Autodesk Fusion 360 part; units mm, degrees
(part 9 of 10)
equation "d738 = abs(( frameZ + 20 mm - ( 0 mm ) ) * -1)"
equation "d739 = abs(( frameZ + 20 mm - ( profileLip ) ) * -1)"
equation "d740 = abs(( ( mountInset ) - ( -profileCavity / 2 ) ) * 1)"
equation "d741 = abs(( frameZ + 20 mm - ( profileTaperStart ) ) * -1)"
equation "d742 = abs(( ( mountInset ) - ( -profileFloor / 2 ) ) * 1)"
equation "d743 = abs(( frameZ + 20 mm - ( profileDepth ) ) * -1)"
equation "d744 = abs(( ( mountInset ) - ( profileFloor / 2 ) ) * 1)"
equation "d745 = abs(( ( mountInset ) - ( profileCavity / 2 ) ) * 1)"
equation "d746 = abs(( ( mountInset ) - ( profileMouth / 2 ) ) * 1)"
equation "d747 = ( 2 * panelHeight - 2 * mountInset + 20 mm ) * 1.0"
equation "d749 = ( mountInset - 10 mm ) * 1.0"
equation "d751 = abs(( ( mountInset ) - 10 mm + ( 0 mm ) ) * 1)"
equation "d752 = abs(( frameZ + 10 mm - ( -profileMouth / 2 ) ) * -1)"
equation "d753 = abs(( ( mountInset ) - 10 mm + ( profileLip ) ) * 1)"
equation "d754 = abs(( frameZ + 10 mm - ( -profileCavity / 2 ) ) * -1)"
equation "d755 = abs(( ( mountInset ) - 10 mm + ( profileTaperStart ) ) * 1)"
equation "d756 = abs(( ( mountInset ) - 10 mm + ( profileDepth ) ) * 1)"
equation "d757 = abs(( frameZ + 10 mm - ( -profileFloor / 2 ) ) * -1)"
equation "d758 = abs(( frameZ + 10 mm - ( profileFloor / 2 ) ) * -1)"
equation "d759 = abs(( frameZ + 10 mm - ( profileCavity / 2 ) ) * -1)"
equation "d760 = abs(( frameZ + 10 mm - ( profileMouth / 2 ) ) * -1)"
equation "d761 = ( 2 * panelHeight - 2 * mountInset + 20 mm ) * 1.0"
equation "d763 = ( mountInset - 10 mm ) * 1.0"
equation "d765 = abs(( mountInset ) * 1)"
equation "d766 = abs(( frameZ + 10 mm ) * -1)"
equation "d767 = profileBore"
equation "d768 = ( 2 * panelHeight - 2 * mountInset + 20 mm ) * 1.0"
equation "d770 = ( mountInset - 10 mm ) * 1.0"
equation "d772 = abs(( ( panelWidth ) - 10 mm ) * 1)"
equation "d773 = abs(( frameZ ) * -1)"
equation "d774 = abs(( ( panelWidth ) + 10 mm ) * 1)"
equation "d775 = abs(( frameZ + 20 mm ) * -1)"
equation "d776 = ( 2 * panelHeight - 2 * mountInset + 20 mm ) * 1.0"
equation "d778 = ( mountInset - 10 mm ) * 1.0"
equation "d780 = abs(( ( panelWidth ) + ( -profileMouth / 2 ) ) * 1)"
equation "d781 = abs(( frameZ + ( 0 mm ) ) * -1)"
equation "d782 = abs(( frameZ + ( profileLip ) ) * -1)"
equation "d783 = abs(( ( panelWidth ) + ( -profileCavity / 2 ) ) * 1)"
equation "d784 = abs(( frameZ + ( profileTaperStart ) ) * -1)"
equation "d785 = abs(( ( panelWidth ) + ( -profileFloor / 2 ) ) * 1)"
equation "d786 = abs(( frameZ + ( profileDepth ) ) * -1)"
equation "d787 = abs(( ( panelWidth ) + ( profileFloor / 2 ) ) * 1)"
equation "d788 = abs(( ( panelWidth ) + ( profileCavity / 2 ) ) * 1)"
equation "d789 = abs(( ( panelWidth ) + ( profileMouth / 2 ) ) * 1)"
equation "d790 = ( 2 * panelHeight - 2 * mountInset + 20 mm ) * 1.0"
equation "d792 = ( mountInset - 10 mm ) * 1.0"
equation "d794 = abs(( ( panelWidth ) + 10 mm - ( 0 mm ) ) * 1)"
equation "d795 = abs(( frameZ + 10 mm + ( -profileMouth / 2 ) ) * -1)"
equation "d796 = abs(( ( panelWidth ) + 10 mm - ( profileLip ) ) * 1)"
equation "d797 = abs(( frameZ + 10 mm + ( -profileCavity / 2 ) ) * -1)"
equation "d798 = abs(( ( panelWidth ) + 10 mm - ( profileTaperStart ) ) * 1)"
equation "d799 = abs(( ( panelWidth ) + 10 mm - ( profileDepth ) ) * 1)"
equation "d800 = abs(( frameZ + 10 mm + ( -profileFloor / 2 ) ) * -1)"
equation "d801 = abs(( frameZ + 10 mm + ( profileFloor / 2 ) ) * -1)"
equation "d802 = abs(( frameZ + 10 mm + ( profileCavity / 2 ) ) * -1)"
equation "d803 = abs(( frameZ + 10 mm + ( profileMouth / 2 ) ) * -1)"
equation "d804 = ( 2 * panelHeight - 2 * mountInset + 20 mm ) * 1.0"
equation "d806 = ( mountInset - 10 mm ) * 1.0"
equation "d808 = abs(( ( panelWidth ) - ( -profileMouth / 2 ) ) * 1)"
equation "d809 = abs(( frameZ + 20 mm - ( 0 mm ) ) * -1)"
equation "d810 = abs(( frameZ + 20 mm - ( profileLip ) ) * -1)"
equation "d811 = abs(( ( panelWidth ) - ( -profileCavity / 2 ) ) * 1)"
equation "d812 = abs(( frameZ + 20 mm - ( profileTaperStart ) ) * -1)"
equation "d813 = abs(( ( panelWidth ) - ( -profileFloor / 2 ) ) * 1)"
equation "d814 = abs(( frameZ + 20 mm - ( profileDepth ) ) * -1)"
equation "d815 = abs(( ( panelWidth ) - ( profileFloor / 2 ) ) * 1)"
equation "d816 = abs(( ( panelWidth ) - ( profileCavity / 2 ) ) * 1)"
equation "d817 = abs(( ( panelWidth ) - ( profileMouth / 2 ) ) * 1)"
equation "d818 = ( 2 * panelHeight - 2 * mountInset + 20 mm ) * 1.0"
equation "d820 = ( mountInset - 10 mm ) * 1.0"
equation "d822 = abs(( ( panelWidth ) - 10 mm + ( 0 mm ) ) * 1)"
equation "d823 = abs(( frameZ + 10 mm - ( -profileMouth / 2 ) ) * -1)"
equation "d824 = abs(( ( panelWidth ) - 10 mm + ( profileLip ) ) * 1)"
equation "d825 = abs(( frameZ + 10 mm - ( -profileCavity / 2 ) ) * -1)"
equation "d826 = abs(( ( panelWidth ) - 10 mm + ( profileTaperStart ) ) * 1)"
equation "d827 = abs(( ( panelWidth ) - 10 mm + ( profileDepth ) ) * 1)"
equation "d828 = abs(( frameZ + 10 mm - ( -profileFloor / 2 ) ) * -1)"
equation "d829 = abs(( frameZ + 10 mm - ( profileFloor / 2 ) ) * -1)"
equation "d830 = abs(( frameZ + 10 mm - ( profileCavity / 2 ) ) * -1)"
equation "d831 = abs(( frameZ + 10 mm - ( profileMouth / 2 ) ) * -1)"
equation "d832 = ( 2 * panelHeight - 2 * mountInset + 20 mm ) * 1.0"
equation "d834 = ( mountInset - 10 mm ) * 1.0"
equation "d836 = abs(( panelWidth ) * 1)"
equation "d837 = abs(( frameZ + 10 mm ) * -1)"
equation "d838 = profileBore"
equation "d839 = ( 2 * panelHeight - 2 * mountInset + 20 mm ) * 1.0"
equation "d841 = ( mountInset - 10 mm ) * 1.0"
equation "d843 = abs(( ( 2 * panelWidth - mountInset ) - 10 mm ) * 1)"
equation "d844 = abs(( frameZ ) * -1)"
equation "d845 = abs(( ( 2 * panelWidth - mountInset ) + 10 mm ) * 1)"
equation "d846 = abs(( frameZ + 20 mm ) * -1)"
equation "d847 = ( 2 * panelHeight - 2 * mountInset + 20 mm ) * 1.0"
equation "d849 = ( mountInset - 10 mm ) * 1.0"
equation "d851 = abs(( ( 2 * panelWidth - mountInset ) + ( -profileMouth / 2 ) ) * 1)"
equation "d852 = abs(( frameZ + ( 0 mm ) ) * -1)"
equation "d853 = abs(( frameZ + ( profileLip ) ) * -1)"
equation "d854 = abs(( ( 2 * panelWidth - mountInset ) + ( -profileCavity / 2 ) ) * 1)"
equation "d855 = abs(( frameZ + ( profileTaperStart ) ) * -1)"
equation "d856 = abs(( ( 2 * panelWidth - mountInset ) + ( -profileFloor / 2 ) ) * 1)"
equation "d857 = abs(( frameZ + ( profileDepth ) ) * -1)"
equation "d858 = abs(( ( 2 * panelWidth - mountInset ) + ( profileFloor / 2 ) ) * 1)"
equation "d859 = abs(( ( 2 * panelWidth - mountInset ) + ( profileCavity / 2 ) ) * 1)"
equation "d860 = abs(( ( 2 * panelWidth - mountInset ) + ( profileMouth / 2 ) ) * 1)"
equation "d861 = ( 2 * panelHeight - 2 * mountInset + 20 mm ) * 1.0"
equation "d863 = ( mountInset - 10 mm ) * 1.0"
equation "d865 = abs(( ( 2 * panelWidth - mountInset ) + 10 mm - ( 0 mm ) ) * 1)"
equation "d866 = abs(( frameZ + 10 mm + ( -profileMouth / 2 ) ) * -1)"
equation "d867 = abs(( ( 2 * panelWidth - mountInset ) + 10 mm - ( profileLip ) ) * 1)"
equation "d868 = abs(( frameZ + 10 mm + ( -profileCavity / 2 ) ) * -1)"
equation "d869 = abs(( ( 2 * panelWidth - mountInset ) + 10 mm - ( profileTaperStart ) ) * 1)"
equation "d870 = abs(( ( 2 * panelWidth - mountInset ) + 10 mm - ( profileDepth ) ) * 1)"
equation "d871 = abs(( frameZ + 10 mm + ( -profileFloor / 2 ) ) * -1)"
equation "d872 = abs(( frameZ + 10 mm + ( profileFloor / 2 ) ) * -1)"
equation "d873 = abs(( frameZ + 10 mm + ( profileCavity / 2 ) ) * -1)"
equation "d874 = abs(( frameZ + 10 mm + ( profileMouth / 2 ) ) * -1)"
equation "d875 = ( 2 * panelHeight - 2 * mountInset + 20 mm ) * 1.0"
equation "d877 = ( mountInset - 10 mm ) * 1.0"
equation "d879 = abs(( ( 2 * panelWidth - mountInset ) - ( -profileMouth / 2 ) ) * 1)"
equation "d880 = abs(( frameZ + 20 mm - ( 0 mm ) ) * -1)"
equation "d881 = abs(( frameZ + 20 mm - ( profileLip ) ) * -1)"
equation "d882 = abs(( ( 2 * panelWidth - mountInset ) - ( -profileCavity / 2 ) ) * 1)"
equation "d883 = abs(( frameZ + 20 mm - ( profileTaperStart ) ) * -1)"
equation "d884 = abs(( ( 2 * panelWidth - mountInset ) - ( -profileFloor / 2 ) ) * 1)"
equation "d885 = abs(( frameZ + 20 mm - ( profileDepth ) ) * -1)"
equation "d886 = abs(( ( 2 * panelWidth - mountInset ) - ( profileFloor / 2 ) ) * 1)"
equation "d887 = abs(( ( 2 * panelWidth - mountInset ) - ( profileCavity / 2 ) ) * 1)"
equation "d888 = abs(( ( 2 * panelWidth - mountInset ) - ( profileMouth / 2 ) ) * 1)"
equation "d889 = ( 2 * panelHeight - 2 * mountInset + 20 mm ) * 1.0"
equation "d891 = ( mountInset - 10 mm ) * 1.0"
equation "d893 = abs(( ( 2 * panelWidth - mountInset ) - 10 mm + ( 0 mm ) ) * 1)"
equation "d894 = abs(( frameZ + 10 mm - ( -profileMouth / 2 ) ) * -1)"
equation "d895 = abs(( ( 2 * panelWidth - mountInset ) - 10 mm + ( profileLip ) ) * 1)"
equation "d896 = abs(( frameZ + 10 mm - ( -profileCavity / 2 ) ) * -1)"
equation "d897 = abs(( ( 2 * panelWidth - mountInset ) - 10 mm + ( profileTaperStart ) ) * 1)"
equation "d898 = abs(( ( 2 * panelWidth - mountInset ) - 10 mm + ( profileDepth ) ) * 1)"
equation "d899 = abs(( frameZ + 10 mm - ( -profileFloor / 2 ) ) * -1)"
equation "d900 = abs(( frameZ + 10 mm - ( profileFloor / 2 ) ) * -1)"
equation "d901 = abs(( frameZ + 10 mm - ( profileCavity / 2 ) ) * -1)"
equation "d902 = abs(( frameZ + 10 mm - ( profileMouth / 2 ) ) * -1)"
equation "d903 = ( 2 * panelHeight - 2 * mountInset + 20 mm ) * 1.0"
equation "d905 = ( mountInset - 10 mm ) * 1.0"
equation "d907 = abs(( 2 * panelWidth - mountInset ) * 1)"
equation "d908 = abs(( frameZ + 10 mm ) * -1)"
equation "d909 = profileBore"
equation "d910 = ( 2 * panelHeight - 2 * mountInset + 20 mm ) * 1.0"
equation "d912 = ( mountInset + 10 mm ) * 1.0"
equation "d914 = abs(( frameZ ) * -1)"
equation "d915 = abs(( ( mountInset ) - 10 mm ) * 1)"
equation "d916 = abs(( ( mountInset ) + 10 mm ) * 1)"
equation "d917 = abs(( frameZ + 20 mm ) * -1)"
equation "d918 = ( panelWidth - ( mountInset ) - 20 mm ) * 1.0"
equation "d920 = ( mountInset + 10 mm ) * 1.0"
equation "d922 = abs(( frameZ + ( 0 mm ) ) * -1)"
equation "d923 = abs(( ( mountInset ) + ( -profileMouth / 2 ) ) * 1)"
equation "d924 = abs(( frameZ + ( profileLip ) ) * -1)"
equation "d925 = abs(( ( mountInset ) + ( -profileCavity / 2 ) ) * 1)"
equation "d926 = abs(( frameZ + ( profileTaperStart ) ) * -1)"
equation "d927 = abs(( frameZ + ( profileDepth ) ) * -1)"
equation "d928 = abs(( ( mountInset ) + ( -profileFloor / 2 ) ) * 1)"
equation "d929 = abs(( ( mountInset ) + ( profileFloor / 2 ) ) * 1)"
equation "d930 = abs(( ( mountInset ) + ( profileCavity / 2 ) ) * 1)"
equation "d931 = abs(( ( mountInset ) + ( profileMouth / 2 ) ) * 1)"
equation "d932 = ( panelWidth - ( mountInset ) - 20 mm ) * 1.0"
equation "d934 = ( mountInset + 10 mm ) * 1.0"
equation "d936 = abs(( frameZ + 10 mm + ( -profileMouth / 2 ) ) * -1)"
equation "d937 = abs(( ( mountInset ) + 10 mm - ( 0 mm ) ) * 1)"
equation "d938 = abs(( ( mountInset ) + 10 mm - ( profileLip ) ) * 1)"
equation "d939 = abs(( frameZ + 10 mm + ( -profileCavity / 2 ) ) * -1)"
equation "d940 = abs(( ( mountInset ) + 10 mm - ( profileTaperStart ) ) * 1)"
equation "d941 = abs(( frameZ + 10 mm + ( -profileFloor / 2 ) ) * -1)"
equation "d942 = abs(( ( mountInset ) + 10 mm - ( profileDepth ) ) * 1)"
equation "d943 = abs(( frameZ + 10 mm + ( profileFloor / 2 ) ) * -1)"
equation "d944 = abs(( frameZ + 10 mm + ( profileCavity / 2 ) ) * -1)"
equation "d945 = abs(( frameZ + 10 mm + ( profileMouth / 2 ) ) * -1)"
equation "d946 = ( panelWidth - ( mountInset ) - 20 mm ) * 1.0"
equation "d948 = ( mountInset + 10 mm ) * 1.0"
equation "d950 = abs(( frameZ + 20 mm - ( 0 mm ) ) * -1)"
equation "d951 = abs(( ( mountInset ) - ( -profileMouth / 2 ) ) * 1)"
equation "d952 = abs(( frameZ + 20 mm - ( profileLip ) ) * -1)"
equation "d953 = abs(( ( mountInset ) - ( -profileCavity / 2 ) ) * 1)"
equation "d954 = abs(( frameZ + 20 mm - ( profileTaperStart ) ) * -1)"
equation "d955 = abs(( frameZ + 20 mm - ( profileDepth ) ) * -1)"
equation "d956 = abs(( ( mountInset ) - ( -profileFloor / 2 ) ) * 1)"
equation "d957 = abs(( ( mountInset ) - ( profileFloor / 2 ) ) * 1)"
equation "d958 = abs(( ( mountInset ) - ( profileCavity / 2 ) ) * 1)"
equation "d959 = abs(( ( mountInset ) - ( profileMouth / 2 ) ) * 1)"
equation "d960 = ( panelWidth - ( mountInset ) - 20 mm ) * 1.0"
equation "d962 = ( mountInset + 10 mm ) * 1.0"
equation "d964 = abs(( frameZ + 10 mm - ( -profileMouth / 2 ) ) * -1)"
equation "d965 = abs(( ( mountInset ) - 10 mm + ( 0 mm ) ) * 1)"
equation "d966 = abs(( ( mountInset ) - 10 mm + ( profileLip ) ) * 1)"
equation "d967 = abs(( frameZ + 10 mm - ( -profileCavity / 2 ) ) * -1)"
equation "d968 = abs(( ( mountInset ) - 10 mm + ( profileTaperStart ) ) * 1)"
equation "d969 = abs(( frameZ + 10 mm - ( -profileFloor / 2 ) ) * -1)"
equation "d970 = abs(( ( mountInset ) - 10 mm + ( profileDepth ) ) * 1)"
equation "d971 = abs(( frameZ + 10 mm - ( profileFloor / 2 ) ) * -1)"
equation "d972 = abs(( frameZ + 10 mm - ( profileCavity / 2 ) ) * -1)"
equation "d973 = abs(( frameZ + 10 mm - ( profileMouth / 2 ) ) * -1)"
equation "d974 = ( panelWidth - ( mountInset ) - 20 mm ) * 1.0"
equation "d976 = ( mountInset + 10 mm ) * 1.0"
equation "d978 = abs(( frameZ + 10 mm ) * -1)"
equation "d979 = abs(( mountInset ) * 1)"
equation "d980 = profileBore"
equation "d981 = ( panelWidth - ( mountInset ) - 20 mm ) * 1.0"
equation "d983 = ( panelWidth + 10 mm ) * 1.0"
equation "d985 = abs(( frameZ ) * -1)"
equation "d986 = abs(( ( mountInset ) - 10 mm ) * 1)"
equation "d987 = abs(( ( mountInset ) + 10 mm ) * 1)"
equation "d988 = abs(( frameZ + 20 mm ) * -1)"
equation "d989 = ( 2 * panelWidth - mountInset - ( panelWidth ) - 20 mm ) * 1.0"
equation "d991 = ( panelWidth + 10 mm ) * 1.0"
equation "d993 = abs(( frameZ + ( 0 mm ) ) * -1)"
equation "d994 = abs(( ( mountInset ) + ( -profileMouth / 2 ) ) * 1)"
equation "d995 = abs(( frameZ + ( profileLip ) ) * -1)"
equation "d996 = abs(( ( mountInset ) + ( -profileCavity / 2 ) ) * 1)"
equation "d997 = abs(( frameZ + ( profileTaperStart ) ) * -1)"
equation "d998 = abs(( frameZ + ( profileDepth ) ) * -1)"
equation "d999 = abs(( ( mountInset ) + ( -profileFloor / 2 ) ) * 1)"
equation "d1000 = abs(( ( mountInset ) + ( profileFloor / 2 ) ) * 1)"
equation "d1001 = abs(( ( mountInset ) + ( profileCavity / 2 ) ) * 1)"
equation "d1002 = abs(( ( mountInset ) + ( profileMouth / 2 ) ) * 1)"
equation "d1003 = ( 2 * panelWidth - mountInset - ( panelWidth ) - 20 mm ) * 1.0"
equation "d1005 = ( panelWidth + 10 mm ) * 1.0"
equation "d1007 = abs(( frameZ + 10 mm + ( -profileMouth / 2 ) ) * -1)"
equation "d1008 = abs(( ( mountInset ) + 10 mm - ( 0 mm ) ) * 1)"
equation "d1009 = abs(( ( mountInset ) + 10 mm - ( profileLip ) ) * 1)"
equation "d1010 = abs(( frameZ + 10 mm + ( -profileCavity / 2 ) ) * -1)"
equation "d1011 = abs(( ( mountInset ) + 10 mm - ( profileTaperStart ) ) * 1)"
equation "d1012 = abs(( frameZ + 10 mm + ( -profileFloor / 2 ) ) * -1)"
equation "d1013 = abs(( ( mountInset ) + 10 mm - ( profileDepth ) ) * 1)"
equation "d1014 = abs(( frameZ + 10 mm + ( profileFloor / 2 ) ) * -1)"
equation "d1015 = abs(( frameZ + 10 mm + ( profileCavity / 2 ) ) * -1)"
equation "d1016 = abs(( frameZ + 10 mm + ( profileMouth / 2 ) ) * -1)"
equation "d1017 = ( 2 * panelWidth - mountInset - ( panelWidth ) - 20 mm ) * 1.0"
equation "d1019 = ( panelWidth + 10 mm ) * 1.0"
equation "d1021 = abs(( frameZ + 20 mm - ( 0 mm ) ) * -1)"
equation "d1022 = abs(( ( mountInset ) - ( -profileMouth / 2 ) ) * 1)"
equation "d1023 = abs(( frameZ + 20 mm - ( profileLip ) ) * -1)"
equation "d1024 = abs(( ( mountInset ) - ( -profileCavity / 2 ) ) * 1)"
equation "d1025 = abs(( frameZ + 20 mm - ( profileTaperStart ) ) * -1)"
equation "d1026 = abs(( frameZ + 20 mm - ( profileDepth ) ) * -1)"
equation "d1027 = abs(( ( mountInset ) - ( -profileFloor / 2 ) ) * 1)"
equation "d1028 = abs(( ( mountInset ) - ( profileFloor / 2 ) ) * 1)"
equation "d1029 = abs(( ( mountInset ) - ( profileCavity / 2 ) ) * 1)"
equation "d1030 = abs(( ( mountInset ) - ( profileMouth / 2 ) ) * 1)"
equation "d1031 = ( 2 * panelWidth - mountInset - ( panelWidth ) - 20 mm ) * 1.0"
equation "d1033 = ( panelWidth + 10 mm ) * 1.0"
equation "d1035 = abs(( frameZ + 10 mm - ( -profileMouth / 2 ) ) * -1)"
equation "d1036 = abs(( ( mountInset ) - 10 mm + ( 0 mm ) ) * 1)"
equation "d1037 = abs(( ( mountInset ) - 10 mm + ( profileLip ) ) * 1)"
equation "d1038 = abs(( frameZ + 10 mm - ( -profileCavity / 2 ) ) * -1)"
equation "d1039 = abs(( ( mountInset ) - 10 mm + ( profileTaperStart ) ) * 1)"
equation "d1040 = abs(( frameZ + 10 mm - ( -profileFloor / 2 ) ) * -1)"
equation "d1041 = abs(( ( mountInset ) - 10 mm + ( profileDepth ) ) * 1)"
equation "d1042 = abs(( frameZ + 10 mm - ( profileFloor / 2 ) ) * -1)"
equation "d1043 = abs(( frameZ + 10 mm - ( profileCavity / 2 ) ) * -1)"
equation "d1044 = abs(( frameZ + 10 mm - ( profileMouth / 2 ) ) * -1)"
equation "d1045 = ( 2 * panelWidth - mountInset - ( panelWidth ) - 20 mm ) * 1.0"
equation "d1047 = ( panelWidth + 10 mm ) * 1.0"
equation "d1049 = abs(( frameZ + 10 mm ) * -1)"
equation "d1050 = abs(( mountInset ) * 1)"
equation "d1051 = profileBore"
equation "d1052 = ( 2 * panelWidth - mountInset - ( panelWidth ) - 20 mm ) * 1.0"
equation "d1054 = ( mountInset + 10 mm ) * 1.0"
equation "d1056 = abs(( frameZ ) * -1)"
equation "d1057 = abs(( ( 2 * panelHeight - mountInset ) - 10 mm ) * 1)"
equation "d1058 = abs(( ( 2 * panelHeight - mountInset ) + 10 mm ) * 1)"
equation "d1059 = abs(( frameZ + 20 mm ) * -1)"
equation "d1060 = ( panelWidth - ( mountInset ) - 20 mm ) * 1.0"
equation "d1062 = ( mountInset + 10 mm ) * 1.0"
equation "d1064 = abs(( frameZ + ( 0 mm ) ) * -1)"
equation "d1065 = abs(( ( 2 * panelHeight - mountInset ) + ( -profileMouth / 2 ) ) * 1)"
equation "d1066 = abs(( frameZ + ( profileLip ) ) * -1)"
equation "d1067 = abs(( ( 2 * panelHeight - mountInset ) + ( -profileCavity / 2 ) ) * 1)"
equation "d1068 = abs(( frameZ + ( profileTaperStart ) ) * -1)"
equation "d1069 = abs(( frameZ + ( profileDepth ) ) * -1)"
equation "d1070 = abs(( ( 2 * panelHeight - mountInset ) + ( -profileFloor / 2 ) ) * 1)"
equation "d1071 = abs(( ( 2 * panelHeight - mountInset ) + ( profileFloor / 2 ) ) * 1)"
equation "d1072 = abs(( ( 2 * panelHeight - mountInset ) + ( profileCavity / 2 ) ) * 1)"
equation "d1073 = abs(( ( 2 * panelHeight - mountInset ) + ( profileMouth / 2 ) ) * 1)"
equation "d1074 = ( panelWidth - ( mountInset ) - 20 mm ) * 1.0"
equation "d1076 = ( mountInset + 10 mm ) * 1.0"
equation "d1078 = abs(( frameZ + 10 mm + ( -profileMouth / 2 ) ) * -1)"
equation "d1079 = abs(( ( 2 * panelHeight - mountInset ) + 10 mm - ( 0 mm ) ) * 1)"
equation "d1080 = abs(( ( 2 * panelHeight - mountInset ) + 10 mm - ( profileLip ) ) * 1)"
equation "d1081 = abs(( frameZ + 10 mm + ( -profileCavity / 2 ) ) * -1)"
equation "d1082 = abs(( ( 2 * panelHeight - mountInset ) + 10 mm - ( profileTaperStart ) ) * 1)"
equation "d1083 = abs(( frameZ + 10 mm + ( -profileFloor / 2 ) ) * -1)"
equation "d1084 = abs(( ( 2 * panelHeight - mountInset ) + 10 mm - ( profileDepth ) ) * 1)"
equation "d1085 = abs(( frameZ + 10 mm + ( profileFloor / 2 ) ) * -1)"
equation "d1086 = abs(( frameZ + 10 mm + ( profileCavity / 2 ) ) * -1)"
equation "d1087 = abs(( frameZ + 10 mm + ( profileMouth / 2 ) ) * -1)"
equation "d1088 = ( panelWidth - ( mountInset ) - 20 mm ) * 1.0"
equation "d1090 = ( mountInset + 10 mm ) * 1.0"
equation "d1092 = abs(( frameZ + 20 mm - ( 0 mm ) ) * -1)"
equation "d1093 = abs(( ( 2 * panelHeight - mountInset ) - ( -profileMouth / 2 ) ) * 1)"
equation "d1094 = abs(( frameZ + 20 mm - ( profileLip ) ) * -1)"
equation "d1095 = abs(( ( 2 * panelHeight - mountInset ) - ( -profileCavity / 2 ) ) * 1)"
equation "d1096 = abs(( frameZ + 20 mm - ( profileTaperStart ) ) * -1)"
equation "d1097 = abs(( frameZ + 20 mm - ( profileDepth ) ) * -1)"
equation "d1098 = abs(( ( 2 * panelHeight - mountInset ) - ( -profileFloor / 2 ) ) * 1)"
equation "d1099 = abs(( ( 2 * panelHeight - mountInset ) - ( profileFloor / 2 ) ) * 1)"
equation "d1100 = abs(( ( 2 * panelHeight - mountInset ) - ( profileCavity / 2 ) ) * 1)"
equation "d1101 = abs(( ( 2 * panelHeight - mountInset ) - ( profileMouth / 2 ) ) * 1)"
equation "d1102 = ( panelWidth - ( mountInset ) - 20 mm ) * 1.0"
equation "d1104 = ( mountInset + 10 mm ) * 1.0"
equation "d1106 = abs(( frameZ + 10 mm - ( -profileMouth / 2 ) ) * -1)"
equation "d1107 = abs(( ( 2 * panelHeight - mountInset ) - 10 mm + ( 0 mm ) ) * 1)"
equation "d1108 = abs(( ( 2 * panelHeight - mountInset ) - 10 mm + ( profileLip ) ) * 1)"
equation "d1109 = abs(( frameZ + 10 mm - ( -profileCavity / 2 ) ) * -1)"
equation "d1110 = abs(( ( 2 * panelHeight - mountInset ) - 10 mm + ( profileTaperStart ) ) * 1)"
equation "d1111 = abs(( frameZ + 10 mm - ( -profileFloor / 2 ) ) * -1)"
equation "d1112 = abs(( ( 2 * panelHeight - mountInset ) - 10 mm + ( profileDepth ) ) * 1)"
equation "d1113 = abs(( frameZ + 10 mm - ( profileFloor / 2 ) ) * -1)"
equation "d1114 = abs(( frameZ + 10 mm - ( profileCavity / 2 ) ) * -1)"
equation "d1115 = abs(( frameZ + 10 mm - ( profileMouth / 2 ) ) * -1)"
equation "d1116 = ( panelWidth - ( mountInset ) - 20 mm ) * 1.0"
equation "d1118 = ( mountInset + 10 mm ) * 1.0"
equation "d1120 = abs(( frameZ + 10 mm ) * -1)"
equation "d1121 = abs(( 2 * panelHeight - mountInset ) * 1)"
equation "d1122 = profileBore"
equation "d1123 = ( panelWidth - ( mountInset ) - 20 mm ) * 1.0"
equation "d1125 = ( panelWidth + 10 mm ) * 1.0"
equation "d1127 = abs(( frameZ ) * -1)"
equation "d1128 = abs(( ( 2 * panelHeight - mountInset ) - 10 mm ) * 1)"
equation "d1129 = abs(( ( 2 * panelHeight - mountInset ) + 10 mm ) * 1)"
equation "d1130 = abs(( frameZ + 20 mm ) * -1)"
equation "d1131 = ( 2 * panelWidth - mountInset - ( panelWidth ) - 20 mm ) * 1.0"
equation "d1133 = ( panelWidth + 10 mm ) * 1.0"
equation "d1135 = abs(( frameZ + ( 0 mm ) ) * -1)"
equation "d1136 = abs(( ( 2 * panelHeight - mountInset ) + ( -profileMouth / 2 ) ) * 1)"
equation "d1137 = abs(( frameZ + ( profileLip ) ) * -1)"
equation "d1138 = abs(( ( 2 * panelHeight - mountInset ) + ( -profileCavity / 2 ) ) * 1)"
equation "d1139 = abs(( frameZ + ( profileTaperStart ) ) * -1)"
equation "d1140 = abs(( frameZ + ( profileDepth ) ) * -1)"
equation "d1141 = abs(( ( 2 * panelHeight - mountInset ) + ( -profileFloor / 2 ) ) * 1)"
equation "d1142 = abs(( ( 2 * panelHeight - mountInset ) + ( profileFloor / 2 ) ) * 1)"
equation "d1143 = abs(( ( 2 * panelHeight - mountInset ) + ( profileCavity / 2 ) ) * 1)"
equation "d1144 = abs(( ( 2 * panelHeight - mountInset ) + ( profileMouth / 2 ) ) * 1)"
equation "d1145 = ( 2 * panelWidth - mountInset - ( panelWidth ) - 20 mm ) * 1.0"
equation "d1147 = ( panelWidth + 10 mm ) * 1.0"
equation "d1149 = abs(( frameZ + 10 mm + ( -profileMouth / 2 ) ) * -1)"
equation "d1150 = abs(( ( 2 * panelHeight - mountInset ) + 10 mm - ( 0 mm ) ) * 1)"
equation "d1151 = abs(( ( 2 * panelHeight - mountInset ) + 10 mm - ( profileLip ) ) * 1)"
equation "d1152 = abs(( frameZ + 10 mm + ( -profileCavity / 2 ) ) * -1)"
equation "d1153 = abs(( ( 2 * panelHeight - mountInset ) + 10 mm - ( profileTaperStart ) ) * 1)"
equation "d1154 = abs(( frameZ + 10 mm + ( -profileFloor / 2 ) ) * -1)"
equation "d1155 = abs(( ( 2 * panelHeight - mountInset ) + 10 mm - ( profileDepth ) ) * 1)"
equation "d1156 = abs(( frameZ + 10 mm + ( profileFloor / 2 ) ) * -1)"
equation "d1157 = abs(( frameZ + 10 mm + ( profileCavity / 2 ) ) * -1)"
equation "d1158 = abs(( frameZ + 10 mm + ( profileMouth / 2 ) ) * -1)"
equation "d1159 = ( 2 * panelWidth - mountInset - ( panelWidth ) - 20 mm ) * 1.0"
equation "d1161 = ( panelWidth + 10 mm ) * 1.0"
equation "d1163 = abs(( frameZ + 20 mm - ( 0 mm ) ) * -1)"
equation "d1164 = abs(( ( 2 * panelHeight - mountInset ) - ( -profileMouth / 2 ) ) * 1)"
equation "d1165 = abs(( frameZ + 20 mm - ( profileLip ) ) * -1)"
equation "d1166 = abs(( ( 2 * panelHeight - mountInset ) - ( -profileCavity / 2 ) ) * 1)"
equation "d1167 = abs(( frameZ + 20 mm - ( profileTaperStart ) ) * -1)"
equation "d1168 = abs(( frameZ + 20 mm - ( profileDepth ) ) * -1)"
equation "d1169 = abs(( ( 2 * panelHeight - mountInset ) - ( -profileFloor / 2 ) ) * 1)"
equation "d1170 = abs(( ( 2 * panelHeight - mountInset ) - ( profileFloor / 2 ) ) * 1)"
equation "d1171 = abs(( ( 2 * panelHeight - mountInset ) - ( profileCavity / 2 ) ) * 1)"
equation "d1172 = abs(( ( 2 * panelHeight - mountInset ) - ( profileMouth / 2 ) ) * 1)"
equation "d1173 = ( 2 * panelWidth - mountInset - ( panelWidth ) - 20 mm ) * 1.0"
equation "d1175 = ( panelWidth + 10 mm ) * 1.0"
equation "d1177 = abs(( frameZ + 10 mm - ( -profileMouth / 2 ) ) * -1)"
equation "d1178 = abs(( ( 2 * panelHeight - mountInset ) - 10 mm + ( 0 mm ) ) * 1)"
equation "d1179 = abs(( ( 2 * panelHeight - mountInset ) - 10 mm + ( profileLip ) ) * 1)"
equation "d1180 = abs(( frameZ + 10 mm - ( -profileCavity / 2 ) ) * -1)"
equation "d1181 = abs(( ( 2 * panelHeight - mountInset ) - 10 mm + ( profileTaperStart ) ) * 1)"
equation "d1182 = abs(( frameZ + 10 mm - ( -profileFloor / 2 ) ) * -1)"
equation "d1183 = abs(( ( 2 * panelHeight - mountInset ) - 10 mm + ( profileDepth ) ) * 1)"
equation "d1184 = abs(( frameZ + 10 mm - ( profileFloor / 2 ) ) * -1)"
equation "d1185 = abs(( frameZ + 10 mm - ( profileCavity / 2 ) ) * -1)"
equation "d1186 = abs(( frameZ + 10 mm - ( profileMouth / 2 ) ) * -1)"
equation "d1187 = ( 2 * panelWidth - mountInset - ( panelWidth ) - 20 mm ) * 1.0"
equation "d1189 = ( panelWidth + 10 mm ) * 1.0"
equation "d1191 = abs(( frameZ + 10 mm ) * -1)"
equation "d1192 = abs(( 2 * panelHeight - mountInset ) * 1)"
equation "d1193 = profileBore"
equation "d1194 = ( 2 * panelWidth - mountInset - ( panelWidth ) - 20 mm ) * 1.0"
equation "d1300 = -capThickness"
equation "d1302 = abs(mountInset)"
equation "d1303 = abs(mountInset)"
equation "d1304 = capDiameter"
equation "d1305 = capThickness"
equation "d1307 = -capThickness"
equation "d1309 = abs(mountInset)"
equation "d1310 = abs(mountInset)"
equation "d1311 = screwClearance"
equation "d1312 = capThickness"
equation "d1314 = boardThickness"
equation "d1316 = abs(mountInset)"
equation "d1317 = abs(mountInset)"
equation "d1318 = capDiameter"
equation "d1319 = seatThickness"
equation "d1321 = boardThickness"
equation "d1323 = abs(mountInset)"
equation "d1324 = abs(mountInset)"
equation "d1325 = mountBore"
equation "d1326 = seatThickness"
equation "d1328 = boardThickness"
equation "d1330 = abs(mountInset + ( -1 ) * registerOffset)"
equation "d1331 = abs(mountInset + ( -1 ) * registerOffset)"
equation "d1332 = registerPin"
equation "d1333 = -registerPinHeight"
equation "d1335 = boardThickness"
equation "d1337 = abs(mountInset + ( -1 ) * registerOffset)"
equation "d1338 = abs(mountInset + ( 1 ) * registerOffset)"
equation "d1339 = registerPin"
equation "d1340 = -registerPinHeight"
equation "d1342 = boardThickness"
equation "d1344 = abs(mountInset + ( 1 ) * registerOffset)"
equation "d1345 = abs(mountInset + ( -1 ) * registerOffset)"
equation "d1346 = registerPin"
equation "d1347 = -registerPinHeight"
equation "d1349 = boardThickness"
equation "d1351 = abs(mountInset + ( 1 ) * registerOffset)"
equation "d1352 = abs(mountInset + ( 1 ) * registerOffset)"
equation "d1353 = registerPin"
equation "d1354 = -registerPinHeight"
equation "d1356 = abs(mountInset)"
equation "d1357 = abs(mountInset)"
equation "d1359 = boardThickness + seatThickness"
equation "d1361 = boardThickness + seatThickness"
equation "d1363 = abs(mountInset)"
equation "d1364 = abs(mountInset)"
equation "d1366 = hookClearance - seatThickness"
equation "d1368 = abs(mountInset)"
equation "d1369 = abs(mountInset)"
equation "d1370 = screwClearance"
equation "d1371 = frameZ"
equation "d1373 = -capThickness - 3 mm"
equation "d1375 = abs(mountInset)"
equation "d1376 = abs(mountInset)"
equation "d1380 = -capThickness"
equation "d1382 = abs(mountInset)"
equation "d1383 = abs(mountInset)"
equation "d1385 = frameZ + capThickness + 5 mm"
equation "d1387 = frameZ + profileLip"
equation "d1389 = abs(mountInset - nutWidth / 2)"
equation "d1390 = abs(mountInset - nutLength / 2)"
equation "d1391 = nutWidth"
equation "d1392 = nutLength"
equation "d1393 = nutThickness"
equation "d1395 = frameZ + profileLip"
equation "d1397 = abs(mountInset)"
equation "d1398 = abs(mountInset)"
equation "d1400 = nutThickness"
equation "d1402 = -capThickness"
equation "d1404 = abs(mountInset)"
equation "d1405 = abs(panelHeight)"
equation "d1406 = capDiameter"
equation "d1407 = capThickness"
equation "d1409 = -capThickness"
equation "d1411 = abs(mountInset)"
equation "d1412 = abs(panelHeight)"
equation "d1413 = screwClearance"
equation "d1414 = capThickness"
equation "d1416 = boardThickness"
equation "d1418 = abs(mountInset)"
equation "d1419 = abs(panelHeight)"
equation "d1420 = capDiameter"
equation "d1421 = seatThickness"
equation "d1423 = boardThickness"
equation "d1425 = abs(mountInset)"
equation "d1426 = abs(panelHeight)"
equation "d1427 = mountBore"
equation "d1428 = seatThickness"
equation "d1430 = boardThickness"
equation "d1432 = abs(mountInset + ( -1 ) * registerOffset)"
equation "d1433 = abs(panelHeight + ( -1 ) * registerOffset)"
equation "d1434 = registerPin"
equation "d1435 = -registerPinHeight"
equation "d1437 = boardThickness"
equation "d1439 = abs(mountInset + ( -1 ) * registerOffset)"
equation "d1440 = abs(panelHeight + ( 1 ) * registerOffset)"
equation "d1441 = registerPin"
equation "d1442 = -registerPinHeight"
equation "d1444 = boardThickness"
equation "d1446 = abs(mountInset + ( 1 ) * registerOffset)"
equation "d1447 = abs(panelHeight + ( -1 ) * registerOffset)"
equation "d1448 = registerPin"
equation "d1449 = -registerPinHeight"
equation "d1451 = boardThickness"
equation "d1453 = abs(mountInset + ( 1 ) * registerOffset)"
equation "d1454 = abs(panelHeight + ( 1 ) * registerOffset)"
equation "d1455 = registerPin"
equation "d1456 = -registerPinHeight"
equation "d1458 = abs(mountInset)"
equation "d1459 = abs(panelHeight)"
equation "d1461 = boardThickness + seatThickness"
equation "d1463 = boardThickness + seatThickness"
equation "d1465 = abs(mountInset)"
equation "d1466 = abs(panelHeight)"
equation "d1468 = hookClearance - seatThickness"
equation "d1470 = abs(mountInset)"
equation "d1471 = abs(panelHeight)"
equation "d1472 = screwClearance"
equation "d1473 = frameZ"
equation "d1475 = -capThickness - 3 mm"
equation "d1477 = abs(mountInset)"
equation "d1478 = abs(panelHeight)"
equation "d1482 = -capThickness"
equation "d1484 = abs(mountInset)"
equation "d1485 = abs(panelHeight)"
equation "d1487 = frameZ + capThickness + 5 mm"
equation "d1489 = frameZ + profileLip"
equation "d1491 = abs(mountInset - nutWidth / 2)"
equation "d1492 = abs(panelHeight - nutLength / 2)"
equation "d1493 = nutWidth"
equation "d1494 = nutLength"
equation "d1495 = nutThickness"
equation "d1497 = frameZ + profileLip"
equation "d1499 = abs(mountInset)"
equation "d1500 = abs(panelHeight)"
equation "d1502 = nutThickness"
equation "d1504 = -capThickness"
equation "d1506 = abs(mountInset)"
equation "d1507 = abs(2 * panelHeight - mountInset)"
equation "d1508 = capDiameter"
equation "d1509 = capThickness"
equation "d1511 = -capThickness"
equation "d1513 = abs(mountInset)"
equation "d1514 = abs(2 * panelHeight - mountInset)"
equation "d1515 = screwClearance"
equation "d1516 = capThickness"
equation "d1518 = boardThickness"
equation "d1520 = abs(mountInset)"
equation "d1521 = abs(2 * panelHeight - mountInset)"
equation "d1522 = capDiameter"
equation "d1523 = seatThickness"
equation "d1525 = boardThickness"
equation "d1527 = abs(mountInset)"
equation "d1528 = abs(2 * panelHeight - mountInset)"
equation "d1529 = mountBore"
equation "d1530 = seatThickness"
equation "d1532 = boardThickness"
equation "d1534 = abs(mountInset + ( -1 ) * registerOffset)"
equation "d1535 = abs(2 * panelHeight - mountInset + ( -1 ) * registerOffset)"
equation "d1536 = registerPin"
equation "d1537 = -registerPinHeight"
equation "d1539 = boardThickness"
equation "d1541 = abs(mountInset + ( -1 ) * registerOffset)"
equation "d1542 = abs(2 * panelHeight - mountInset + ( 1 ) * registerOffset)"
equation "d1543 = registerPin"
equation "d1544 = -registerPinHeight"
equation "d1546 = boardThickness"
equation "d1548 = abs(mountInset + ( 1 ) * registerOffset)"
equation "d1549 = abs(2 * panelHeight - mountInset + ( -1 ) * registerOffset)"
equation "d1550 = registerPin"
equation "d1551 = -registerPinHeight"
equation "d1553 = boardThickness"
equation "d1555 = abs(mountInset + ( 1 ) * registerOffset)"
equation "d1556 = abs(2 * panelHeight - mountInset + ( 1 ) * registerOffset)"
equation "d1557 = registerPin"
equation "d1558 = -registerPinHeight"
equation "d1560 = abs(mountInset)"
equation "d1561 = abs(2 * panelHeight - mountInset)"
equation "d1563 = boardThickness + seatThickness"
equation "d1565 = boardThickness + seatThickness"
equation "d1567 = abs(mountInset)"
equation "d1568 = abs(2 * panelHeight - mountInset)"
equation "d1570 = hookClearance - seatThickness"
equation "d1572 = abs(mountInset)"
equation "d1573 = abs(2 * panelHeight - mountInset)"
equation "d1574 = screwClearance"
equation "d1575 = frameZ"
equation "d1577 = -capThickness - 3 mm"
equation "d1579 = abs(mountInset)"
equation "d1580 = abs(2 * panelHeight - mountInset)"
equation "d1584 = -capThickness"
equation "d1586 = abs(mountInset)"
equation "d1587 = abs(2 * panelHeight - mountInset)"
equation "d1589 = frameZ + capThickness + 5 mm"
equation "d1591 = frameZ + profileLip"
equation "d1593 = abs(mountInset - nutWidth / 2)"
equation "d1594 = abs(2 * panelHeight - mountInset - nutLength / 2)"
equation "d1595 = nutWidth"
equation "d1596 = nutLength"
equation "d1597 = nutThickness"
equation "d1599 = frameZ + profileLip"
equation "d1601 = abs(mountInset)"
equation "d1602 = abs(2 * panelHeight - mountInset)"
equation "d1604 = nutThickness"
equation "d1606 = -capThickness"
equation "d1608 = abs(panelWidth)"
equation "d1609 = abs(mountInset)"
equation "d1610 = capDiameter"
equation "d1611 = capThickness"
equation "d1613 = -capThickness"
equation "d1615 = abs(panelWidth)"
equation "d1616 = abs(mountInset)"
equation "d1617 = screwClearance"
equation "d1618 = capThickness"
equation "d1620 = boardThickness"
equation "d1622 = abs(panelWidth)"
equation "d1623 = abs(mountInset)"
equation "d1624 = capDiameter"
equation "d1625 = seatThickness"
equation "d1627 = boardThickness"
equation "d1629 = abs(panelWidth)"
equation "d1630 = abs(mountInset)"
equation "d1631 = mountBore"
equation "d1632 = seatThickness"
equation "d1634 = boardThickness"
equation "d1636 = abs(panelWidth + ( -1 ) * registerOffset)"
equation "d1637 = abs(mountInset + ( -1 ) * registerOffset)"
equation "d1638 = registerPin"
equation "d1639 = -registerPinHeight"
equation "d1641 = boardThickness"
equation "d1643 = abs(panelWidth + ( -1 ) * registerOffset)"
equation "d1644 = abs(mountInset + ( 1 ) * registerOffset)"
equation "d1645 = registerPin"
equation "d1646 = -registerPinHeight"
equation "d1648 = boardThickness"
equation "d1650 = abs(panelWidth + ( 1 ) * registerOffset)"
equation "d1651 = abs(mountInset + ( -1 ) * registerOffset)"
equation "d1652 = registerPin"
equation "d1653 = -registerPinHeight"
equation "d1655 = boardThickness"
equation "d1657 = abs(panelWidth + ( 1 ) * registerOffset)"
equation "d1658 = abs(mountInset + ( 1 ) * registerOffset)"
equation "d1659 = registerPin"
equation "d1660 = -registerPinHeight"
equation "d1662 = abs(panelWidth)"
equation "d1663 = abs(mountInset)"
equation "d1665 = boardThickness + seatThickness"
equation "d1667 = boardThickness + seatThickness"
equation "d1669 = abs(panelWidth)"
equation "d1670 = abs(mountInset)"
equation "d1672 = hookClearance - seatThickness"
equation "d1674 = abs(panelWidth)"
equation "d1675 = abs(mountInset)"
equation "d1676 = screwClearance"
equation "d1677 = frameZ"
equation "d1679 = -capThickness - 3 mm"
equation "d1681 = abs(panelWidth)"
equation "d1682 = abs(mountInset)"
equation "d1686 = -capThickness"
equation "d1688 = abs(panelWidth)"
equation "d1689 = abs(mountInset)"
equation "d1691 = frameZ + capThickness + 5 mm"
equation "d1693 = frameZ + profileLip"
equation "d1695 = abs(panelWidth - nutWidth / 2)"
equation "d1696 = abs(mountInset - nutLength / 2)"
equation "d1697 = nutWidth"
equation "d1698 = nutLength"
equation "d1699 = nutThickness"
equation "d1701 = frameZ + profileLip"
equation "d1703 = abs(panelWidth)"
equation "d1704 = abs(mountInset)"
equation "d1706 = nutThickness"
equation "d1708 = -capThickness"
equation "d1710 = abs(panelWidth)"
equation "d1711 = abs(panelHeight)"
equation "d1712 = capDiameter"
equation "d1713 = capThickness"
equation "d1715 = -capThickness"
equation "d1717 = abs(panelWidth)"
equation "d1718 = abs(panelHeight)"
equation "d1719 = screwClearance"
equation "d1720 = capThickness"
equation "d1722 = boardThickness"
equation "d1724 = abs(panelWidth)"
equation "d1725 = abs(panelHeight)"
equation "d1726 = capDiameter"
equation "d1727 = seatThickness"
equation "d1729 = boardThickness"
equation "d1731 = abs(panelWidth)"
equation "d1732 = abs(panelHeight)"
equation "d1733 = mountBore"
equation "d1734 = seatThickness"
equation "d1736 = boardThickness"
equation "d1738 = abs(panelWidth + ( -1 ) * registerOffset)"
equation "d1739 = abs(panelHeight + ( -1 ) * registerOffset)"
equation "d1740 = registerPin"
equation "d1741 = -registerPinHeight"
equation "d1743 = boardThickness"
equation "d1745 = abs(panelWidth + ( -1 ) * registerOffset)"
equation "d1746 = abs(panelHeight + ( 1 ) * registerOffset)"
equation "d1747 = registerPin"
equation "d1748 = -registerPinHeight"
equation "d1750 = boardThickness"
equation "d1752 = abs(panelWidth + ( 1 ) * registerOffset)"
equation "d1753 = abs(panelHeight + ( -1 ) * registerOffset)"
equation "d1754 = registerPin"
equation "d1755 = -registerPinHeight"
equation "d1757 = boardThickness"
equation "d1759 = abs(panelWidth + ( 1 ) * registerOffset)"
equation "d1760 = abs(panelHeight + ( 1 ) * registerOffset)"
equation "d1761 = registerPin"
equation "d1762 = -registerPinHeight"
equation "d1764 = abs(panelWidth)"
equation "d1765 = abs(panelHeight)"
equation "d1767 = boardThickness + seatThickness"
equation "d1769 = boardThickness + seatThickness"
equation "d1771 = abs(panelWidth)"
equation "d1772 = abs(panelHeight)"
equation "d1774 = hookClearance - seatThickness"
equation "d1776 = abs(panelWidth)"
equation "d1777 = abs(panelHeight)"
equation "d1778 = screwClearance"
equation "d1779 = frameZ"
equation "d1781 = -capThickness - 3 mm"
equation "d1783 = abs(panelWidth)"
equation "d1784 = abs(panelHeight)"
equation "d1788 = -capThickness"
equation "d1790 = abs(panelWidth)"
equation "d1791 = abs(panelHeight)"
equation "d1793 = frameZ + capThickness + 5 mm"
equation "d1795 = frameZ + profileLip"
equation "d1797 = abs(panelWidth - nutWidth / 2)"
equation "d1798 = abs(panelHeight - nutLength / 2)"
equation "d1799 = nutWidth"
equation "d1800 = nutLength"
equation "d1801 = nutThickness"
equation "d1803 = frameZ + profileLip"
equation "d1805 = abs(panelWidth)"
equation "d1806 = abs(panelHeight)"
equation "d1808 = nutThickness"
equation "d1810 = -capThickness"
equation "d1812 = abs(panelWidth)"
equation "d1813 = abs(2 * panelHeight - mountInset)"
equation "d1814 = capDiameter"
equation "d1815 = capThickness"
equation "d1817 = -capThickness"
equation "d1819 = abs(panelWidth)"
equation "d1820 = abs(2 * panelHeight - mountInset)"
equation "d1821 = screwClearance"
equation "d1822 = capThickness"
equation "d1824 = boardThickness"
equation "d1826 = abs(panelWidth)"
equation "d1827 = abs(2 * panelHeight - mountInset)"
equation "d1828 = capDiameter"
equation "d1829 = seatThickness"
equation "d1831 = boardThickness"
equation "d1833 = abs(panelWidth)"
equation "d1834 = abs(2 * panelHeight - mountInset)"
equation "d1835 = mountBore"
equation "d1836 = seatThickness"
equation "d1838 = boardThickness"
equation "d1840 = abs(panelWidth + ( -1 ) * registerOffset)"
equation "d1841 = abs(2 * panelHeight - mountInset + ( -1 ) * registerOffset)"
equation "d1842 = registerPin"
equation "d1843 = -registerPinHeight"
equation "d1845 = boardThickness"
equation "d1847 = abs(panelWidth + ( -1 ) * registerOffset)"
equation "d1848 = abs(2 * panelHeight - mountInset + ( 1 ) * registerOffset)"
equation "d1849 = registerPin"
equation "d1850 = -registerPinHeight"
equation "d1852 = boardThickness"
equation "d1854 = abs(panelWidth + ( 1 ) * registerOffset)"
equation "d1855 = abs(2 * panelHeight - mountInset + ( -1 ) * registerOffset)"
equation "d1856 = registerPin"
equation "d1857 = -registerPinHeight"
equation "d1859 = boardThickness"
equation "d1861 = abs(panelWidth + ( 1 ) * registerOffset)"
equation "d1862 = abs(2 * panelHeight - mountInset + ( 1 ) * registerOffset)"
equation "d1863 = registerPin"
equation "d1864 = -registerPinHeight"
equation "d1866 = abs(panelWidth)"
equation "d1867 = abs(2 * panelHeight - mountInset)"
equation "d1869 = boardThickness + seatThickness"
equation "d1871 = boardThickness + seatThickness"
equation "d1873 = abs(panelWidth)"
equation "d1874 = abs(2 * panelHeight - mountInset)"
equation "d1876 = hookClearance - seatThickness"
equation "d1878 = abs(panelWidth)"
equation "d1879 = abs(2 * panelHeight - mountInset)"
equation "d1880 = screwClearance"
equation "d1881 = frameZ"
equation "d1883 = -capThickness - 3 mm"
equation "d1885 = abs(panelWidth)"
equation "d1886 = abs(2 * panelHeight - mountInset)"
equation "d1890 = -capThickness"
equation "d1892 = abs(panelWidth)"
equation "d1893 = abs(2 * panelHeight - mountInset)"
equation "d1895 = frameZ + capThickness + 5 mm"
equation "d1897 = frameZ + profileLip"
equation "d1899 = abs(panelWidth - nutWidth / 2)"
equation "d1900 = abs(2 * panelHeight - mountInset - nutLength / 2)"
equation "d1901 = nutWidth"
equation "d1902 = nutLength"
equation "d1903 = nutThickness"
equation "d1905 = frameZ + profileLip"
equation "d1907 = abs(panelWidth)"
equation "d1908 = abs(2 * panelHeight - mountInset)"
equation "d1910 = nutThickness"
equation "d1912 = -capThickness"
equation "d1914 = abs(2 * panelWidth - mountInset)"
equation "d1915 = abs(mountInset)"
equation "d1916 = capDiameter"
equation "d1917 = capThickness"
equation "d1919 = -capThickness"
equation "d1921 = abs(2 * panelWidth - mountInset)"
equation "d1922 = abs(mountInset)"
equation "d1923 = screwClearance"
equation "d1924 = capThickness"
equation "d1926 = boardThickness"
equation "d1928 = abs(2 * panelWidth - mountInset)"
equation "d1929 = abs(mountInset)"
equation "d1930 = capDiameter"
equation "d1931 = seatThickness"
equation "d1933 = boardThickness"
equation "d1935 = abs(2 * panelWidth - mountInset)"
equation "d1936 = abs(mountInset)"
equation "d1937 = mountBore"
equation "d1938 = seatThickness"
equation "d1940 = boardThickness"
equation "d1942 = abs(2 * panelWidth - mountInset + ( -1 ) * registerOffset)"
equation "d1943 = abs(mountInset + ( -1 ) * registerOffset)"
equation "d1944 = registerPin"
equation "d1945 = -registerPinHeight"
equation "d1947 = boardThickness"
equation "d1949 = abs(2 * panelWidth - mountInset + ( -1 ) * registerOffset)"
equation "d1950 = abs(mountInset + ( 1 ) * registerOffset)"
equation "d1951 = registerPin"
equation "d1952 = -registerPinHeight"
equation "d1954 = boardThickness"
equation "d1956 = abs(2 * panelWidth - mountInset + ( 1 ) * registerOffset)"
equation "d1957 = abs(mountInset + ( -1 ) * registerOffset)"
equation "d1958 = registerPin"
equation "d1959 = -registerPinHeight"
equation "d1961 = boardThickness"
equation "d1963 = abs(2 * panelWidth - mountInset + ( 1 ) * registerOffset)"
equation "d1964 = abs(mountInset + ( 1 ) * registerOffset)"
equation "d1965 = registerPin"
equation "d1966 = -registerPinHeight"
equation "d1968 = abs(2 * panelWidth - mountInset)"
equation "d1969 = abs(mountInset)"
equation "d1971 = boardThickness + seatThickness"
equation "d1973 = boardThickness + seatThickness"
equation "d1975 = abs(2 * panelWidth - mountInset)"
equation "d1976 = abs(mountInset)"
equation "d1978 = hookClearance - seatThickness"
equation "d1980 = abs(2 * panelWidth - mountInset)"
equation "d1981 = abs(mountInset)"
equation "d1982 = screwClearance"
equation "d1983 = frameZ"
equation "d1985 = -capThickness - 3 mm"
equation "d1987 = abs(2 * panelWidth - mountInset)"
equation "d1988 = abs(mountInset)"
equation "d1992 = -capThickness"
equation "d1994 = abs(2 * panelWidth - mountInset)"
equation "d1995 = abs(mountInset)"
equation "d1997 = frameZ + capThickness + 5 mm"
equation "d1999 = frameZ + profileLip"
equation "d2001 = abs(2 * panelWidth - mountInset - nutWidth / 2)"
equation "d2002 = abs(mountInset - nutLength / 2)"
equation "d2003 = nutWidth"
equation "d2004 = nutLength"
equation "d2005 = nutThickness"
equation "d2007 = frameZ + profileLip"
equation "d2009 = abs(2 * panelWidth - mountInset)"
equation "d2010 = abs(mountInset)"
equation "d2012 = nutThickness"
equation "d2014 = -capThickness"
equation "d2016 = abs(2 * panelWidth - mountInset)"
equation "d2017 = abs(panelHeight)"
equation "d2018 = capDiameter"
equation "d2019 = capThickness"
equation "d2021 = -capThickness"
equation "d2023 = abs(2 * panelWidth - mountInset)"
equation "d2024 = abs(panelHeight)"
equation "d2025 = screwClearance"
equation "d2026 = capThickness"
equation "d2028 = boardThickness"
equation "d2030 = abs(2 * panelWidth - mountInset)"
equation "d2031 = abs(panelHeight)"
equation "d2032 = capDiameter"
equation "d2033 = seatThickness"
equation "d2035 = boardThickness"
equation "d2037 = abs(2 * panelWidth - mountInset)"
equation "d2038 = abs(panelHeight)"
equation "d2039 = mountBore"
equation "d2040 = seatThickness"
equation "d2042 = boardThickness"
equation "d2044 = abs(2 * panelWidth - mountInset + ( -1 ) * registerOffset)"
equation "d2045 = abs(panelHeight + ( -1 ) * registerOffset)"
equation "d2046 = registerPin"
equation "d2047 = -registerPinHeight"
equation "d2049 = boardThickness"
equation "d2051 = abs(2 * panelWidth - mountInset + ( -1 ) * registerOffset)"
equation "d2052 = abs(panelHeight + ( 1 ) * registerOffset)"
equation "d2053 = registerPin"
equation "d2054 = -registerPinHeight"
equation "d2056 = boardThickness"
equation "d2058 = abs(2 * panelWidth - mountInset + ( 1 ) * registerOffset)"
equation "d2059 = abs(panelHeight + ( -1 ) * registerOffset)"
equation "d2060 = registerPin"
equation "d2061 = -registerPinHeight"
equation "d2063 = boardThickness"
equation "d2065 = abs(2 * panelWidth - mountInset + ( 1 ) * registerOffset)"
equation "d2066 = abs(panelHeight + ( 1 ) * registerOffset)"
equation "d2067 = registerPin"
equation "d2068 = -registerPinHeight"
equation "d2070 = abs(2 * panelWidth - mountInset)"
equation "d2071 = abs(panelHeight)"
equation "d2073 = boardThickness + seatThickness"
equation "d2075 = boardThickness + seatThickness"
equation "d2077 = abs(2 * panelWidth - mountInset)"
equation "d2078 = abs(panelHeight)"
equation "d2080 = hookClearance - seatThickness"
equation "d2082 = abs(2 * panelWidth - mountInset)"
equation "d2083 = abs(panelHeight)"
equation "d2084 = screwClearance"
equation "d2085 = frameZ"
equation "d2087 = -capThickness - 3 mm"
equation "d2089 = abs(2 * panelWidth - mountInset)"
equation "d2090 = abs(panelHeight)"
equation "d2094 = -capThickness"
equation "d2096 = abs(2 * panelWidth - mountInset)"
equation "d2097 = abs(panelHeight)"
equation "d2099 = frameZ + capThickness + 5 mm"
equation "d2101 = frameZ + profileLip"
equation "d2103 = abs(2 * panelWidth - mountInset - nutWidth / 2)"
equation "d2104 = abs(panelHeight - nutLength / 2)"
equation "d2105 = nutWidth"
equation "d2106 = nutLength"
equation "d2107 = nutThickness"
equation "d2109 = frameZ + profileLip"
equation "d2111 = abs(2 * panelWidth - mountInset)"
equation "d2112 = abs(panelHeight)"
equation "d2114 = nutThickness"
equation "d2116 = -capThickness"
equation "d2118 = abs(2 * panelWidth - mountInset)"
equation "d2119 = abs(2 * panelHeight - mountInset)"
equation "d2120 = capDiameter"
equation "d2121 = capThickness"
equation "d2123 = -capThickness"
equation "d2125 = abs(2 * panelWidth - mountInset)"
equation "d2126 = abs(2 * panelHeight - mountInset)"
equation "d2127 = screwClearance"
equation "d2128 = capThickness"
equation "d2130 = boardThickness"
equation "d2132 = abs(2 * panelWidth - mountInset)"
equation "d2133 = abs(2 * panelHeight - mountInset)"
equation "d2134 = capDiameter"
equation "d2135 = seatThickness"
equation "d2137 = boardThickness"
equation "d2139 = abs(2 * panelWidth - mountInset)"
equation "d2140 = abs(2 * panelHeight - mountInset)"
equation "d2141 = mountBore"
equation "d2142 = seatThickness"
equation "d2144 = boardThickness"
equation "d2146 = abs(2 * panelWidth - mountInset + ( -1 ) * registerOffset)"
equation "d2147 = abs(2 * panelHeight - mountInset + ( -1 ) * registerOffset)"
equation "d2148 = registerPin"
equation "d2149 = -registerPinHeight"
equation "d2151 = boardThickness"
equation "d2153 = abs(2 * panelWidth - mountInset + ( -1 ) * registerOffset)"
equation "d2154 = abs(2 * panelHeight - mountInset + ( 1 ) * registerOffset)"
equation "d2155 = registerPin"
equation "d2156 = -registerPinHeight"
equation "d2158 = boardThickness"
equation "d2160 = abs(2 * panelWidth - mountInset + ( 1 ) * registerOffset)"
equation "d2161 = abs(2 * panelHeight - mountInset + ( -1 ) * registerOffset)"
equation "d2162 = registerPin"
equation "d2163 = -registerPinHeight"
equation "d2165 = boardThickness"
equation "d2167 = abs(2 * panelWidth - mountInset + ( 1 ) * registerOffset)"
equation "d2168 = abs(2 * panelHeight - mountInset + ( 1 ) * registerOffset)"
equation "d2169 = registerPin"
equation "d2170 = -registerPinHeight"
equation "d2172 = abs(2 * panelWidth - mountInset)"
equation "d2173 = abs(2 * panelHeight - mountInset)"
equation "d2175 = boardThickness + seatThickness"
equation "d2177 = boardThickness + seatThickness"